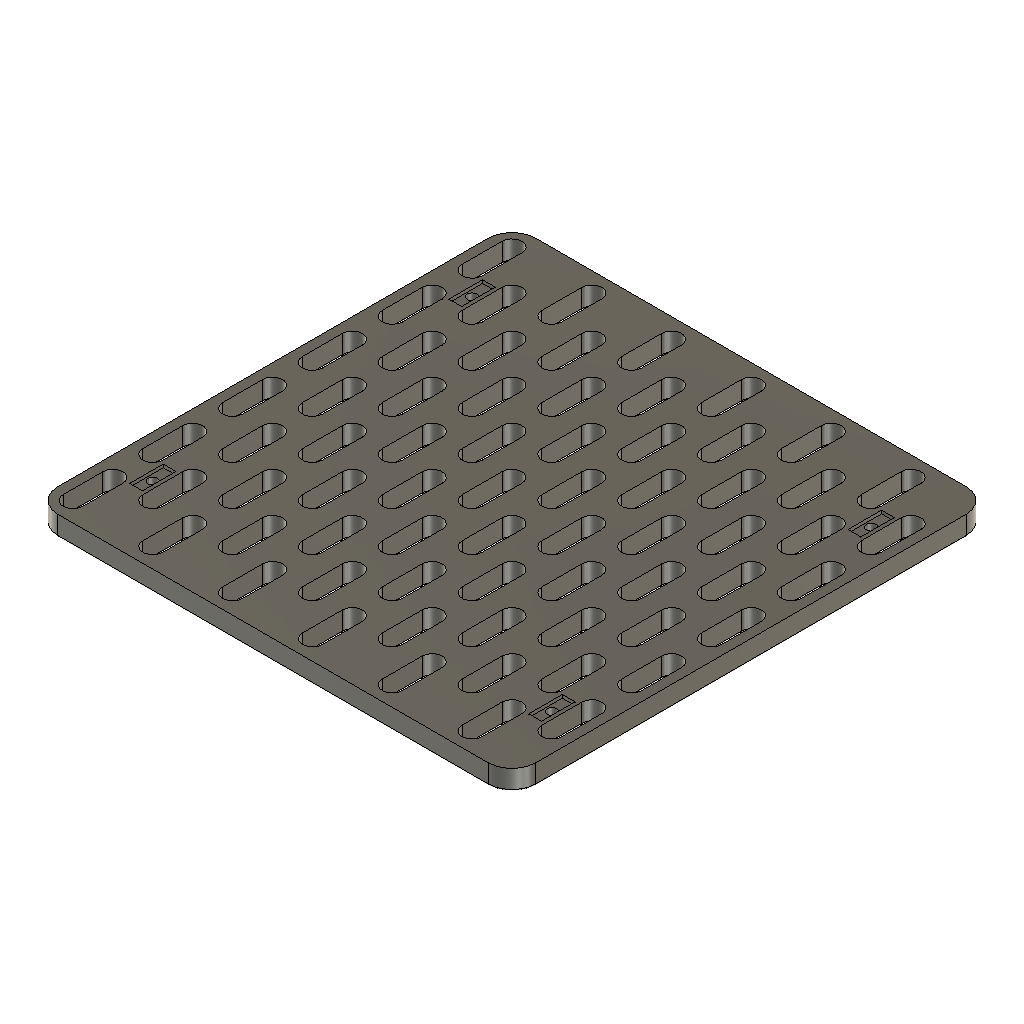
panel-standalone-120 (Autodesk Fusion 360 design; units mm, degrees)
part number: 2026-10-29-11-18-34-200
part number: 2026-10-29-11-18-34-513
Autodesk Fusion 360 part; units mm, degrees
sketch "01 Panel blank sketch" plane through (0, 0, 0) normal (0, 0, 1) x (1, 0, 0) in component "Panel standalone"
  line L0 (0.1, 0.1) -> (119.9, 0.1)
  line L1 (119.9, 0.1) -> (119.9, 119.9)
  line L2 (119.9, 119.9) -> (0.1, 119.9)
  line L3 (0.1, 119.9) -> (0.1, 0.1)
  dimension "d70" = 0.1
  dimension "d71" = 0.1
  dimension "d72" = 119.8
  dimension "d73" = 119.8
  constraint horizontal L0
  constraint vertical L1
  constraint horizontal L2
  constraint vertical L3
  measures "d70" horizontal distance of origin L0.start
  measures "d71" vertical distance of origin L0.start
  measures "d72" horizontal distance of L0.start L0.end
  measures "d73" vertical distance of L0.end L1.end
extrude "01 Panel blank" add sketch "01 Panel blank sketch" along normal blind 5 in component "Panel standalone"
fillet "02 Rounded outer corners" radius 6 4 edges at (0.1, 119.9, 2.5) (119.9, 119.9, 2.5) (119.9, 0.1, 2.5) (0.1, 0.1, 2.5) in component "Panel standalone"
sketch "03 Complete A lattice constrained seed" plane through (0, 0, 0) normal (0, 0, 1) x (1, 0, 0) in component "Panel standalone"
  line L0 (7.5, 5) -> (7.5, 15)
  arc A0 (7.5, 15) -> (2.5, 15) centre (5, 15) ccw
  line L1 (2.5, 15) -> (2.5, 5)
  arc A1 (2.5, 5) -> (7.5, 5) centre (5, 5) ccw
  line L2 (5, 5) -> (5, 15) construction
  line L3 (5, 5) -> (15, 5) construction
  dimension "d78" = 5
  dimension "d79" = 10
  dimension "d80" = 90
  dimension "d81" = 10
  dimension "d82" = 5
  dimension "d83" = 5
  constraint tangent L0 A0
  constraint tangent A0 L1
  constraint tangent L1 A1
  constraint tangent L0 A1
  constraint parallel L0 L1
  constraint horizontal L3
  measures "d78" diameter of A0
  measures "d79" distance of A1.centre A0.centre
  measures "d80" angle of L2 L3
  measures "d81" horizontal distance of A1.centre L3.end
  measures "d82" horizontal distance of origin A1.centre
  measures "d83" vertical distance of origin A1.centre
extrude "03 Complete A lattice through cut" cut sketch "03 Complete A lattice constrained seed" along normal blind 5 in component "Panel standalone"
pattern_linear "03 Complete A lattice lattice" count 6 spacing 20 along (1, 0, 0) count 6 spacing 20 along (0, 1, 0) of "03 Complete A lattice through cut" in component "Panel standalone"
sketch "04 B lattice with finished horizontal edges constrained seed" plane through (0, 0, 0) normal (0, 0, 1) x (1, 0, 0) in component "Panel standalone"
  line L0 (17.5, 15) -> (17.5, 25)
  arc A0 (17.5, 25) -> (12.5, 25) centre (15, 25) ccw
  line L1 (12.5, 25) -> (12.5, 15)
  arc A1 (12.5, 15) -> (17.5, 15) centre (15, 15) ccw
  line L2 (15, 15) -> (15, 25) construction
  line L3 (15, 15) -> (25, 15) construction
  dimension "d90" = 5
  dimension "d91" = 10
  dimension "d92" = 90
  dimension "d93" = 10
  dimension "d94" = 15
  dimension "d95" = 15
  constraint tangent L0 A0
  constraint tangent A0 L1
  constraint tangent L1 A1
  constraint tangent L0 A1
  constraint parallel L0 L1
  constraint horizontal L3
  measures "d90" diameter of A0
  measures "d91" distance of A1.centre A0.centre
  measures "d92" angle of L2 L3
  measures "d93" horizontal distance of A1.centre L3.end
  measures "d94" horizontal distance of origin A1.centre
  measures "d95" vertical distance of origin A1.centre
extrude "04 B lattice with finished horizontal edges through cut" cut sketch "04 B lattice with finished horizontal edges constrained seed" along normal blind 5 in component "Panel standalone"
pattern_linear "04 B lattice with finished horizontal edges lattice" count 6 spacing 20 along (1, 0, 0) count 5 spacing 20 along (0, 1, 0) of "04 B lattice with finished horizontal edges through cut" in component "Panel standalone"
fillet "05 Rounded slot entrances and perimeter" radius 0.4 2 faces at (15.0623, 7.5023, 0) (15.0623, 7.5023, 0) in component "Panel standalone"
sketch "06 M2 through bore sketch" plane through (0, 0, 0) normal (0, 0, 1) x (1, 0, 0) in component "Panel standalone"
  circle A0 centre (10, 20) radius 1.2
  dimension "d104" = 10
  dimension "d105" = 20
  dimension "d106" = 2.4
  measures "d104" horizontal distance of origin A0.centre
  measures "d105" vertical distance of origin A0.centre
  measures "d106" diameter of A0
extrude "06 M2 through bore" cut sketch "06 M2 through bore sketch" along normal blind 5 in component "Panel standalone"
sketch "07 Flush countersink sketch" plane through (0, 0, 0) normal (0, 0, 1) x (1, 0, 0) in component "Panel standalone"
  circle A0 centre (10, 20) radius 2
  dimension "d109" = 10
  dimension "d110" = 20
  dimension "d111" = 4
  measures "d109" horizontal distance of origin A0.centre
  measures "d110" vertical distance of origin A0.centre
  measures "d111" diameter of A0
extrude "07 Flush countersink" cut sketch "07 Flush countersink sketch" along normal blind 0.8 draft -45 in component "Panel standalone"
ref_plane "WorkPlane1" through (0, 0, 5) normal (0, 0, 1) x (1, 0, 0) in component "Panel standalone"
sketch "08 Blind rear registration sketch" plane through (0, 0, 5) normal (0, 0, 1) x (1, 0, 0) in component "Panel standalone"
  line L0 (8.4, 15.8) -> (11.6, 15.8)
  line L1 (11.6, 15.8) -> (11.6, 24.2)
  line L2 (11.6, 24.2) -> (8.4, 24.2)
  line L3 (8.4, 24.2) -> (8.4, 15.8)
  dimension "d116" = 8.4
  dimension "d117" = 15.8
  dimension "d118" = 3.2
  dimension "d119" = 8.4
  constraint horizontal L0
  constraint vertical L1
  constraint horizontal L2
  constraint vertical L3
  measures "d116" horizontal distance of origin L0.start
  measures "d117" vertical distance of origin L0.start
  measures "d118" horizontal distance of L0.start L0.end
  measures "d119" vertical distance of L0.end L1.end
extrude "08 Blind rear registration" cut sketch "08 Blind rear registration sketch" against normal blind 0.8 in component "Panel standalone"
sketch "06 M2 through bore sketch (1)" plane through (0, 0, 0) normal (0, 0, 1) x (1, 0, 0) in component "Panel standalone"
  circle A0 centre (10, 100) radius 1.2
  dimension "d122" = 10
  dimension "d123" = 100
  dimension "d124" = 2.4
  measures "d122" horizontal distance of origin A0.centre
  measures "d123" vertical distance of origin A0.centre
  measures "d124" diameter of A0
extrude "06 M2 through bore (1)" cut sketch "06 M2 through bore sketch (1)" along normal blind 5 in component "Panel standalone"
sketch "07 Flush countersink sketch (1)" plane through (0, 0, 0) normal (0, 0, 1) x (1, 0, 0) in component "Panel standalone"
  circle A0 centre (10, 100) radius 2
  dimension "d127" = 10
  dimension "d128" = 100
  dimension "d129" = 4
  measures "d127" horizontal distance of origin A0.centre
  measures "d128" vertical distance of origin A0.centre
  measures "d129" diameter of A0
extrude "07 Flush countersink (1)" cut sketch "07 Flush countersink sketch (1)" along normal blind 0.8 draft -45 in component "Panel standalone"
ref_plane "WorkPlane2" through (0, 0, 5) normal (0, 0, 1) x (1, 0, 0) in component "Panel standalone"
sketch "08 Blind rear registration sketch (1)" plane through (0, 0, 5) normal (0, 0, 1) x (1, 0, 0) in component "Panel standalone"
  line L0 (8.4, 95.8) -> (11.6, 95.8)
  line L1 (11.6, 95.8) -> (11.6, 104.2)
  line L2 (11.6, 104.2) -> (8.4, 104.2)
  line L3 (8.4, 104.2) -> (8.4, 95.8)
  dimension "d134" = 8.4
  dimension "d135" = 95.8
  dimension "d136" = 3.2
  dimension "d137" = 8.4
  constraint horizontal L0
  constraint vertical L1
  constraint horizontal L2
  constraint vertical L3
  measures "d134" horizontal distance of origin L0.start
  measures "d135" vertical distance of origin L0.start
  measures "d136" horizontal distance of L0.start L0.end
  measures "d137" vertical distance of L0.end L1.end
extrude "08 Blind rear registration (1)" cut sketch "08 Blind rear registration sketch (1)" against normal blind 0.8 in component "Panel standalone"
sketch "06 M2 through bore sketch (2)" plane through (0, 0, 0) normal (0, 0, 1) x (1, 0, 0) in component "Panel standalone"
  circle A0 centre (110, 20) radius 1.2
  dimension "d140" = 110
  dimension "d141" = 20
  dimension "d142" = 2.4
  measures "d140" horizontal distance of origin A0.centre
  measures "d141" vertical distance of origin A0.centre
  measures "d142" diameter of A0
extrude "06 M2 through bore (2)" cut sketch "06 M2 through bore sketch (2)" along normal blind 5 in component "Panel standalone"
sketch "07 Flush countersink sketch (2)" plane through (0, 0, 0) normal (0, 0, 1) x (1, 0, 0) in component "Panel standalone"
  circle A0 centre (110, 20) radius 2
  dimension "d145" = 110
  dimension "d146" = 20
  dimension "d147" = 4
  measures "d145" horizontal distance of origin A0.centre
  measures "d146" vertical distance of origin A0.centre
  measures "d147" diameter of A0
extrude "07 Flush countersink (2)" cut sketch "07 Flush countersink sketch (2)" along normal blind 0.8 draft -45 in component "Panel standalone"
ref_plane "WorkPlane3" through (0, 0, 5) normal (0, 0, 1) x (1, 0, 0) in component "Panel standalone"
sketch "08 Blind rear registration sketch (2)" plane through (0, 0, 5) normal (0, 0, 1) x (1, 0, 0) in component "Panel standalone"
  line L0 (108.4, 15.8) -> (111.6, 15.8)
  line L1 (111.6, 15.8) -> (111.6, 24.2)
  line L2 (111.6, 24.2) -> (108.4, 24.2)
  line L3 (108.4, 24.2) -> (108.4, 15.8)
  dimension "d152" = 108.4
  dimension "d153" = 15.8
  dimension "d154" = 3.2
  dimension "d155" = 8.4
  constraint horizontal L0
  constraint vertical L1
  constraint horizontal L2
  constraint vertical L3
  measures "d152" horizontal distance of origin L0.start
  measures "d153" vertical distance of origin L0.start
  measures "d154" horizontal distance of L0.start L0.end
  measures "d155" vertical distance of L0.end L1.end
extrude "08 Blind rear registration (2)" cut sketch "08 Blind rear registration sketch (2)" against normal blind 0.8 in component "Panel standalone"
sketch "06 M2 through bore sketch (3)" plane through (0, 0, 0) normal (0, 0, 1) x (1, 0, 0) in component "Panel standalone"
  circle A0 centre (110, 100) radius 1.2
  dimension "d158" = 110
  dimension "d159" = 100
  dimension "d160" = 2.4
  measures "d158" horizontal distance of origin A0.centre
  measures "d159" vertical distance of origin A0.centre
  measures "d160" diameter of A0
extrude "06 M2 through bore (3)" cut sketch "06 M2 through bore sketch (3)" along normal blind 5 in component "Panel standalone"
sketch "07 Flush countersink sketch (3)" plane through (0, 0, 0) normal (0, 0, 1) x (1, 0, 0) in component "Panel standalone"
  circle A0 centre (110, 100) radius 2
  dimension "d163" = 110
  dimension "d164" = 100
  dimension "d165" = 4
  measures "d163" horizontal distance of origin A0.centre
  measures "d164" vertical distance of origin A0.centre
  measures "d165" diameter of A0
extrude "07 Flush countersink (3)" cut sketch "07 Flush countersink sketch (3)" along normal blind 0.8 draft -45 in component "Panel standalone"
ref_plane "WorkPlane4" through (0, 0, 5) normal (0, 0, 1) x (1, 0, 0) in component "Panel standalone"
sketch "08 Blind rear registration sketch (3)" plane through (0, 0, 5) normal (0, 0, 1) x (1, 0, 0) in component "Panel standalone"
  line L0 (108.4, 95.8) -> (111.6, 95.8)
  line L1 (111.6, 95.8) -> (111.6, 104.2)
  line L2 (111.6, 104.2) -> (108.4, 104.2)
  line L3 (108.4, 104.2) -> (108.4, 95.8)
  dimension "d170" = 108.4
  dimension "d171" = 95.8
  dimension "d172" = 3.2
  dimension "d173" = 8.4
  constraint horizontal L0
  constraint vertical L1
  constraint horizontal L2
  constraint vertical L3
  measures "d170" horizontal distance of origin L0.start
  measures "d171" vertical distance of origin L0.start
  measures "d172" horizontal distance of L0.start L0.end
  measures "d173" vertical distance of L0.end L1.end
extrude "08 Blind rear registration (3)" cut sketch "08 Blind rear registration sketch (3)" against normal blind 0.8 in component "Panel standalone"
component "Panel standalone" placed x (1, 0, 0) y (0, 1, 0) z (0, 0, 1) at (0, 0, 0)
equation "columns = 6" comment "Even integer 4..14; each cell is 20 mm"
equation "rows = 6" comment "Even integer 4..14"
equation "pitch = 20 mm" comment "Keep for dense SKADIS compatible lattice"
equation "panelWidth = columns * pitch" comment "Nominal module pitch X"
equation "panelHeight = rows * pitch" comment "Nominal module pitch Y"
equation "seamGap = 0.2 mm" comment "Physical envelope shrinks around fixed lattice"
equation "boardThickness = 5 mm" comment "Fit-test with real hooks"
equation "slotWidth = 5 mm" comment "Minimum throat width"
equation "slotHeight = 15 mm" comment "Minimum throat height"
equation "entryRadius = 0.4 mm" comment "Front slot and perimeter edge rounding"
equation "cornerRadius = 6 mm" comment "Plan-view panel corner rounding"
equation "hookClearance = 10 mm" comment "PROVISIONAL unobstructed depth behind board; carriers begin at its rear boundary"
equation "frameZ = carrierZ + carrierThickness" comment "Front extrusion datum"
equation "profileMouth = 6.28 mm" comment "User measured mouth"
equation "profileCavity = 11 mm" comment "User measured widest cavity"
equation "profileDepth = 6.2 mm" comment "User measured face-to-floor depth"
equation "profileFloor = 5.7 mm" comment "User estimate, lower confidence"
equation "profileLip = 1.5 mm" comment "Unmeasured; tentative comparable catalog value"
equation "profileTaperStart = profileDepth - ( profileCavity - profileFloor ) / 2" comment "Assumed 45-degree inner slopes"
equation "profileBore = 5 mm" comment "Unmeasured central bore, reference only"
equation "nutWidth = 8.8 mm" comment "Provisional low-profile METAL T-nut envelope, not old rectangular carrier"
equation "nutLength = 12 mm" comment "End-loaded anti-rotation metal nut envelope"
equation "nutThickness = 2.7 mm" comment "Thin nut reference; fit/load still unverified"
equation "jointLeg = 18 mm" comment "In-bay angle footprint"
equation "jointThickness = 3 mm" comment "Metal bracket thickness"
equation "jointDepth = 16 mm" comment "Bracket depth within 20 mm rail"
equation "sideScrewLength = 8 mm" comment "M5x8 reference; check against actual bracket and nut"
equation "wallTabHeight = 24 mm" comment "Tab along extrusion"
equation "wallTabReach = 22 mm" comment "Tab into open bay"
equation "wallAnchorClearance = 6.5 mm" comment "Placeholder wall anchor interface"
equation "wallDriverDiameter = 12 mm" comment "Clear tool envelope in open bays"
equation "keyDriverDiameter = 5 mm" comment "Short hex-key working-leg envelope"
equation "keyDriverReach = 20 mm" comment "Short hex-key working-leg reach"
equation "supportWidth = 3.2 mm" comment "Prototype blade; two perimeter lines need print review"
equation "supportLength = 12 mm" comment "Compression bearing length"
equation "hookEnvelopeWidth = 6 mm" comment "Conservative provisional continuous hook column"
equation "carrierThickness = 7 mm" comment "Room for captive M2 nut and stock M5x12"
equation "panelClearance = 2.4 mm" comment "M2 clearance"
equation "panelHeadPocket = 4 mm" comment "DIN965 3.8 mm head plus 0.1 mm recess"
equation "carrierHeadPocket = 9.4 mm" comment "DIN965 M5 9.2 mm head plus recess"
equation "carrierBore = 5.5 mm" comment "M5 clearance"
equation "tongueWidth = 2.8 mm" comment "Rear axial registration tongue"
equation "tongueLength = 8 mm" comment "Axial release registration"
equation "tongueDepth = 0.6 mm" comment "Tongue engagement"
equation "registerClearance = 0.2 mm" comment "Each side of printed tongue"
equation "carrierZ = boardThickness + hookClearance" comment "Rear hook cavity boundary"
equation "variantLeft = 1" comment "Finished edge flag; change by rebuilding variant, resize natively"
equation "variantRight = 1" comment "Finished edge flag; change by rebuilding variant, resize natively"
equation "variantBottom = 1" comment "Finished edge flag; change by rebuilding variant, resize natively"
equation "variantTop = 1" comment "Finished edge flag; change by rebuilding variant, resize natively"
equation "d70 = abs(( 0 mm ) + seamGap / 2)"
equation "d71 = abs(( 0 mm ) + seamGap / 2)"
equation "d72 = panelWidth - seamGap"
equation "d73 = panelHeight - seamGap"
equation "d74 = boardThickness"
equation "d77 = cornerRadius"
equation "d78 = slotWidth"
equation "d79 = slotHeight - slotWidth"
equation "d81 = pitch / 2"
equation "d82 = abs(( 0 mm ) + pitch / 4)"
equation "d83 = abs(( ( 0 mm ) + pitch / 2 ) - ( slotHeight - slotWidth ) / 2)"
equation "d84 = boardThickness"
equation "d86 = columns"
equation "d87 = rows"
equation "d88 = pitch"
equation "d89 = pitch"
equation "d90 = slotWidth"
equation "d91 = slotHeight - slotWidth"
equation "d93 = pitch / 2"
equation "d94 = abs(( 0 mm ) + 3 * pitch / 4)"
equation "d95 = abs(( ( 0 mm ) + pitch * variantBottom ) - ( slotHeight - slotWidth ) / 2)"
equation "d96 = boardThickness"
equation "d98 = columns"
equation "d99 = rows + 1 - variantBottom - variantTop"
equation "d100 = pitch"
equation "d101 = pitch"
equation "d103 = entryRadius"
equation "d104 = abs(( 0 mm ) + pitch / 2)"
equation "d105 = abs(( 0 mm ) + pitch)"
equation "d106 = panelClearance"
equation "d107 = boardThickness"
equation "d109 = abs(( 0 mm ) + pitch / 2)"
equation "d110 = abs(( 0 mm ) + pitch)"
equation "d111 = panelHeadPocket"
equation "d112 = ( panelHeadPocket - panelClearance ) / 2"
equation "d114 = boardThickness"
equation "d116 = abs(( 0 mm ) + pitch / 2 - tongueWidth / 2 - registerClearance)"
equation "d117 = abs(( 0 mm ) + pitch - tongueLength / 2 - registerClearance)"
equation "d118 = tongueWidth + 2 * registerClearance"
equation "d119 = tongueLength + 2 * registerClearance"
equation "d120 = -tongueDepth - 0.2 mm"
equation "d122 = abs(( 0 mm ) + pitch / 2)"
equation "d123 = abs(( 0 mm ) + panelHeight - pitch)"
equation "d124 = panelClearance"
equation "d125 = boardThickness"
equation "d127 = abs(( 0 mm ) + pitch / 2)"
equation "d128 = abs(( 0 mm ) + panelHeight - pitch)"
equation "d129 = panelHeadPocket"
equation "d130 = ( panelHeadPocket - panelClearance ) / 2"
equation "d132 = boardThickness"
equation "d134 = abs(( 0 mm ) + pitch / 2 - tongueWidth / 2 - registerClearance)"
equation "d135 = abs(( 0 mm ) + panelHeight - pitch - tongueLength / 2 - registerClearance)"
equation "d136 = tongueWidth + 2 * registerClearance"
equation "d137 = tongueLength + 2 * registerClearance"
equation "d138 = -tongueDepth - 0.2 mm"
equation "d140 = abs(( 0 mm ) + panelWidth - pitch / 2)"
equation "d141 = abs(( 0 mm ) + pitch)"
equation "d142 = panelClearance"
equation "d143 = boardThickness"
equation "d145 = abs(( 0 mm ) + panelWidth - pitch / 2)"
equation "d146 = abs(( 0 mm ) + pitch)"
equation "d147 = panelHeadPocket"
equation "d148 = ( panelHeadPocket - panelClearance ) / 2"
equation "d150 = boardThickness"
equation "d152 = abs(( 0 mm ) + panelWidth - pitch / 2 - tongueWidth / 2 - registerClearance)"
equation "d153 = abs(( 0 mm ) + pitch - tongueLength / 2 - registerClearance)"
equation "d154 = tongueWidth + 2 * registerClearance"
equation "d155 = tongueLength + 2 * registerClearance"
equation "d156 = -tongueDepth - 0.2 mm"
equation "d158 = abs(( 0 mm ) + panelWidth - pitch / 2)"
equation "d159 = abs(( 0 mm ) + panelHeight - pitch)"
equation "d160 = panelClearance"
equation "d161 = boardThickness"
equation "d163 = abs(( 0 mm ) + panelWidth - pitch / 2)"
equation "d164 = abs(( 0 mm ) + panelHeight - pitch)"
equation "d165 = panelHeadPocket"
equation "d166 = ( panelHeadPocket - panelClearance ) / 2"
equation "d168 = boardThickness"
equation "d170 = abs(( 0 mm ) + panelWidth - pitch / 2 - tongueWidth / 2 - registerClearance)"
equation "d171 = abs(( 0 mm ) + panelHeight - pitch - tongueLength / 2 - registerClearance)"
equation "d172 = tongueWidth + 2 * registerClearance"
equation "d173 = tongueLength + 2 * registerClearance"
equation "d174 = -tongueDepth - 0.2 mm"
